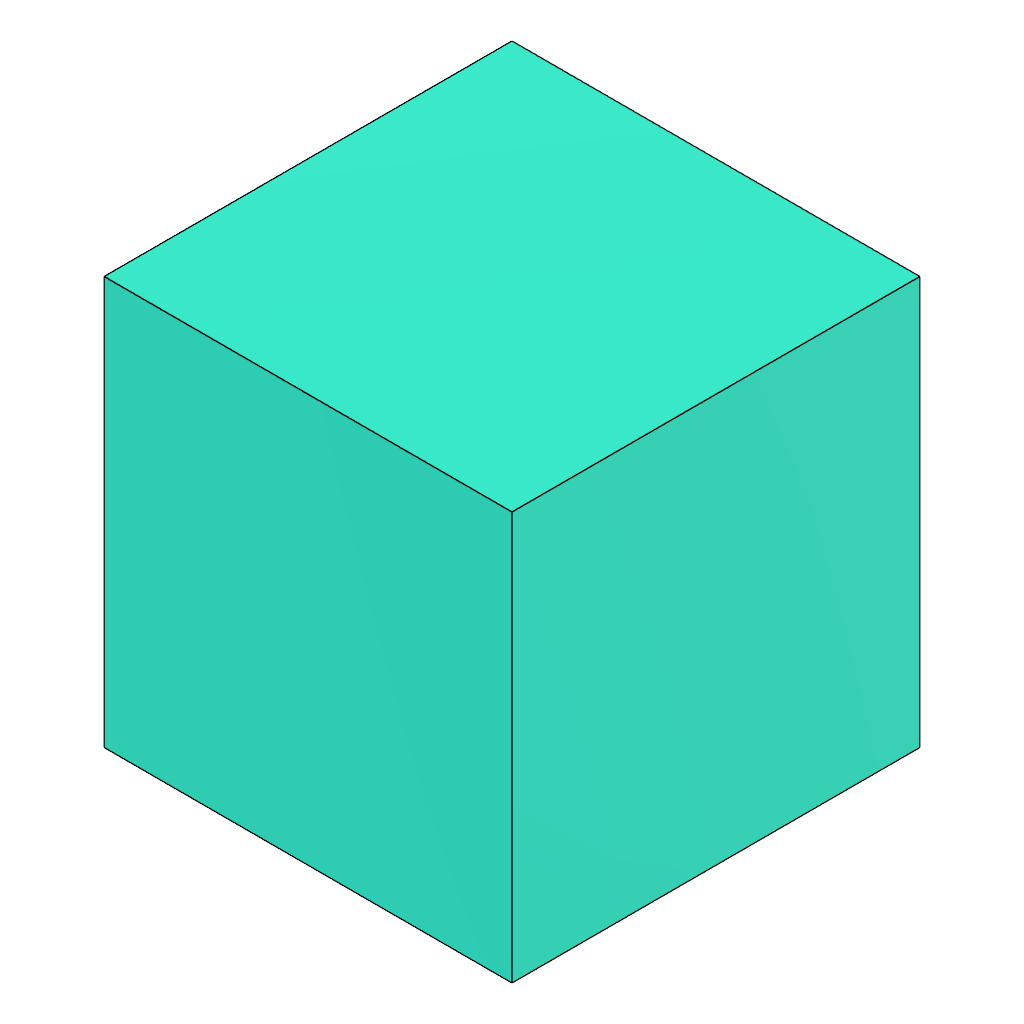
level -1 cube (Autodesk Fusion 360 design; units mm, degrees)
part number: 2026-10-11-11-00-30-425
Autodesk Fusion 360 part; units mm, degrees
box "BoxPrimitive2" add length 100 width 100 height 100 placed x (0, 0, -1) y (-1, 0, 0) z (0, 1, 0) at (0, 0, 0)
